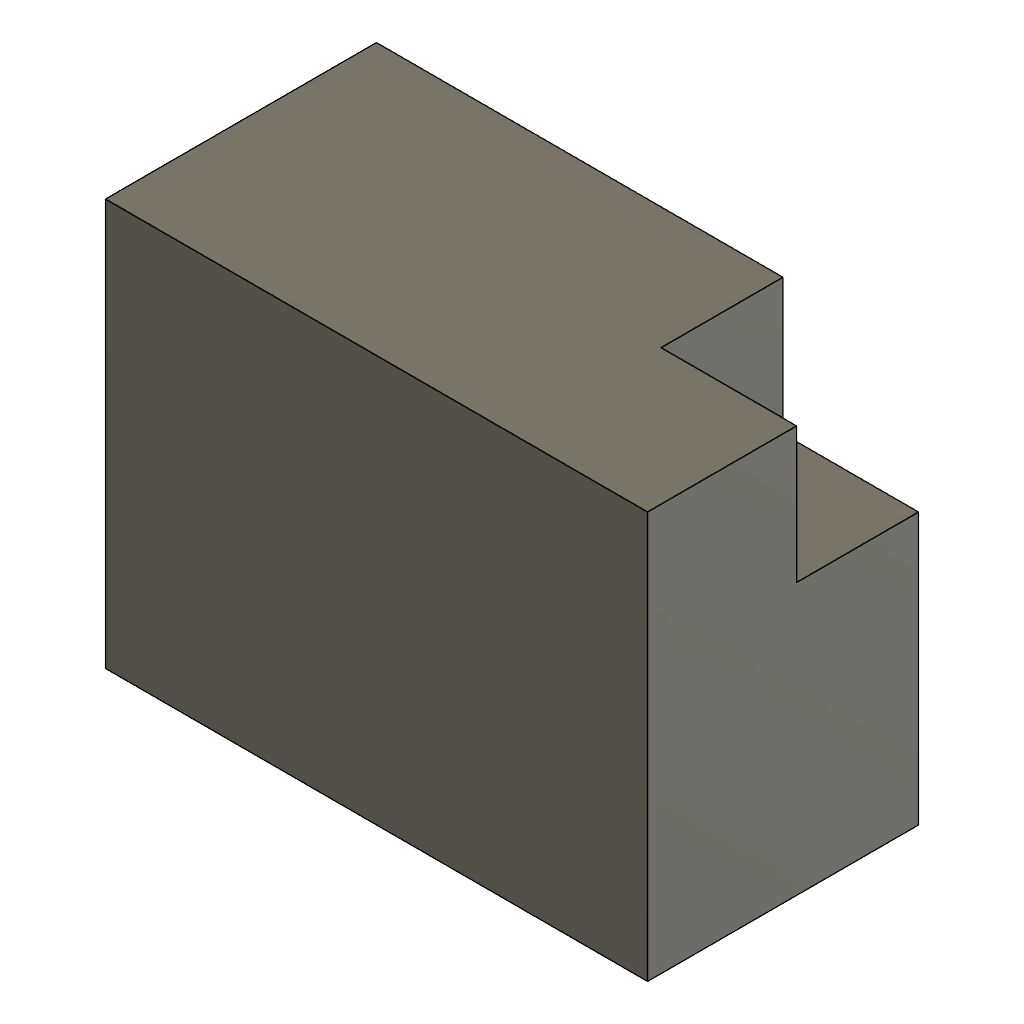
CornerPocket (Autodesk Fusion 360 design; units mm, degrees)
part number: 2026-11-22-11-52-12-073
Autodesk Fusion 360 part; units mm, degrees
sketch "Base sketch" plane through (0, 0, 0) normal (0, 0, 1) x (1, 0, 0)
  line L0 (0, 0) -> (40, 0)
  line L1 (40, 0) -> (40, 30)
  line L2 (40, 30) -> (0, 30)
  line L3 (0, 30) -> (0, 0)
extrude "Base" add sketch "Base sketch" along normal blind 20
sketch "Corner sketch" plane through (0, 0, 0) normal (0, 0, 1) x (1, 0, 0)
  line L0 (30, 20) -> (50, 20)
  line L1 (50, 20) -> (50, 40)
  line L2 (50, 40) -> (30, 40)
  line L3 (30, 40) -> (30, 20)
extrude "Corner" cut sketch "Corner sketch" along normal blind 9
